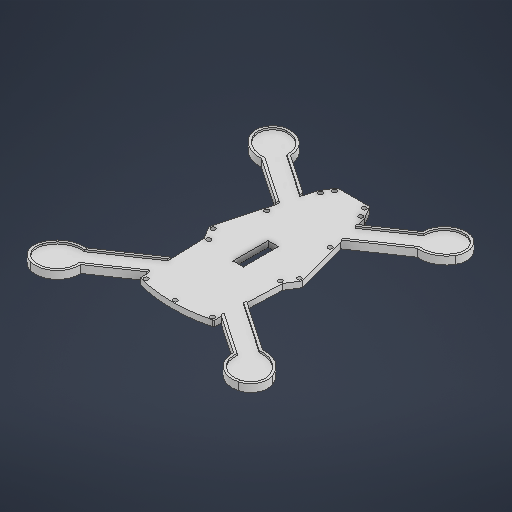
# Autodesk Inventor part: baseFinal
Saved by Autodesk Inventor 2026 (Build 300175000, 175)
## iProperties
Created: 2026-10-27
Part Number: baseFinal
Material: Genérico
Document SubType Name: Modeling
Designer: Juan David
Density: 1 g/cm^3
Appearance: Valor por defecto
Author: Juan David
Autodesk Inventor part; units mm, degrees
ref_plane "YZ Plane" through (0, 0, 0) normal (1, 0, 0) x (0, 1, 0)
ref_plane "XZ Plane" through (0, 0, 0) normal (0, 1, 0) x (-1, 0, 0)
ref_plane "XY Plane" through (0, 0, 0) normal (0, 0, 1) x (1, 0, 0)
sketch "Boceto1" plane through (0, 0, 0) normal (0, 1, 0) x (-1, 0, 0)
  line L0 (0, -150) -> (0, 150) construction
  line L1 (30.9916, 147.5712) -> (32.9123, 92.5712)
  arc A0 (30.9916, 147.5712) -> (30.2412, 148.5049) centre (29.9922, 147.5363) ccw
  line L2 (30.9916, 147.5712) -> (30.9916, 113.5172) construction
  line L3 (32.9123, 92.5712) -> (32.9123, 56.093) construction
  line L4 (32.9123, 92.5712) -> (39.3857, 82.2916)
  line L5 (39.3857, 82.2916) -> (19.8163, 10.2644)
  line L6 (19.8163, 10.2644) -> (19.8163, 47.3861) construction
  line L7 (19.8163, 10.2644) -> (13.6, 0)
  line L8 (13.6, 0) -> (13.6, 36.8341) construction
  line L9 (0, 0) -> (13.6, 0)
  line L10 (31.8621, 149.7984) -> (31.8621, 95.4867) construction
  line L11 (31.165, 142.6049) -> (64.2011, 165.1574)
  line L12 (31.8878, 121.9093) -> (74.0679, 150.7042)
  line L13 (54.2398, 179.7492) -> (74.1624, 150.5657) construction
  arc A1 (87.3177, 184.2934) -> (64.2011, 165.1574) centre (82.7685, 166.2583) ccw
  arc A2 (97.2377, 165.1659) -> (87.3177, 184.2934) centre (83.7957, 170.3307) ccw
  arc A3 (74.0679, 150.7042) -> (97.2377, 165.1659) centre (76.0608, 173.3027) ccw
  line L14 (31.165, 142.6049) -> (43.7776, 124.1294) construction
  line L15 (-112.3542, 46.9093) -> (112.3542, 46.9093) construction
  line L16 (130.9594, 121.9093) -> (-67.1839, 121.9093) construction
  line L17 (-124.1928, 84.4093) -> (124.1928, 84.4093) construction
  line L18 (45.548, -17.1271) -> (65.3642, 11.9007) construction
  arc A4 (55.4975, -2.5526) -> (75.66, -20.7594) centre (74.0946, -2.2254) ccw
  arc A5 (75.66, -20.7594) -> (86.7708, 1.04) centre (74.4481, -6.4105) ccw
  arc A6 (86.7708, 1.04) -> (65.3642, 11.9007) centre (67.3572, -10.6978) ccw
  line L19 (55.4975, -2.5526) -> (22.4614, 20)
  line L20 (22.4614, 20) -> (22.4614, -42.0773) construction
  line L21 (65.3642, 11.9007) -> (27.3176, 37.8738)
  line L22 (35.803, 41.6229) -> (22.4614, 20) construction
  line L23 (-30.9916, 147.5712) -> (-32.9123, 92.5712)
  arc A7 (-30.2412, 148.5049) -> (-30.9916, 147.5712) centre (-29.9922, 147.5363) ccw
  line L24 (-30.9916, 147.5712) -> (-30.9916, 113.5172) construction
  line L25 (-32.9123, 92.5712) -> (-32.9123, 56.093) construction
  line L26 (-32.9123, 92.5712) -> (-39.3857, 82.2916)
  line L27 (-39.3857, 82.2916) -> (-19.8163, 10.2644)
  line L28 (-19.8163, 10.2644) -> (-19.8163, 47.3861) construction
  line L29 (-19.8163, 10.2644) -> (-13.6, 0)
  line L30 (-13.6, 0) -> (-13.6, 36.8341) construction
  line L31 (0, 0) -> (-13.6, 0)
  line L32 (-31.8621, 149.7984) -> (-31.8621, 95.4867) construction
  line L33 (-31.165, 142.6049) -> (-64.2011, 165.1574)
  line L34 (-31.8878, 121.9093) -> (-74.0679, 150.7042)
  line L35 (-54.2398, 179.7492) -> (-74.1624, 150.5657) construction
  arc A8 (-64.2011, 165.1574) -> (-87.3177, 184.2934) centre (-82.7685, 166.2583) ccw
  arc A9 (-87.3177, 184.2934) -> (-97.2377, 165.1659) centre (-83.7957, 170.3307) ccw
  arc A10 (-97.2377, 165.1659) -> (-74.0679, 150.7042) centre (-76.0608, 173.3027) ccw
  line L36 (-31.165, 142.6049) -> (-43.7776, 124.1294) construction
  line L37 (-45.548, -17.1271) -> (-65.3642, 11.9007) construction
  arc A11 (-65.3642, 11.9007) -> (-86.7708, 1.04) centre (-67.3572, -10.6978) ccw
  arc A12 (-75.66, -20.7594) -> (-55.4975, -2.5526) centre (-74.0946, -2.2254) ccw
  arc A13 (-86.7708, 1.04) -> (-75.66, -20.7594) centre (-74.4481, -6.4105) ccw
  line L38 (-55.4975, -2.5526) -> (-22.4614, 20)
  line L39 (-22.4614, 20) -> (-22.4614, -42.0773) construction
  line L40 (-65.3642, 11.9007) -> (-27.3176, 37.8738)
  line L41 (-35.803, 41.6229) -> (-22.4614, 20) construction
  arc A14 (30.2412, 148.5049) -> (-30.2412, 148.5049) centre (0, 30.8422) ccw
  line L42 (4.35, 97.0416) -> (-4.35, 97.0416)
  line L43 (-4.35, 97.0416) -> (-4.35, 67.5416)
  line L44 (-4.35, 67.5416) -> (4.35, 67.5416)
  line L45 (4.35, 67.5416) -> (4.35, 97.0416)
  line L46 (4.35, 97.0416) -> (-4.35, 67.5416) construction
  line L47 (-4.35, 97.0416) -> (4.35, 67.5416) construction
  point P0 (31.8621, 122.6425)
  point P1 (96.5789, 176.9603)
  point P2 (0, 46.9093)
  point P3 (0, 84.4093)
  point P4 (-31.8621, 122.6425)
  point P5 (-96.5789, 176.9603)
  point P6 (0, 152.329)
  point P7 (0, 82.2916)
  point P8 (87.2778, -12.9496)
  dimension "d0" = 300
  dimension "d2" = 1
  dimension "d4" = 2
  dimension "d9" = 15.2
  dimension "d10" = 31.2
  dimension "d11" = 13.6
  dimension "d14" = 32.2
  dimension "d19" = 55
  dimension "d20" = 12
  dimension "d22" = 55.68
  dimension "d23" = 90
  dimension "d24" = 40
  dimension "d25" = 17.5
  dimension "d26" = 18.6
  dimension "d27" = 14.4
  dimension "d28" = 22.6863
  dimension "d29" = 5.9
  dimension "d37" = 75
  dimension "d38" = 37.5
  dimension "d41" = 55.68
  dimension "d43" = 40
  dimension "d44" = 90
  dimension "d45" = 17.5
  dimension "d47" = 20
  dimension "d48" = 121.4867
  dimension "d49" = 152.3289
  dimension "d50" = 8.7
  dimension "d51" = 29.5
  dimension "d54" = 10.2796
  dimension "d55" = 67.5416
  dimension "d69" = 67.4958
  dimension "d70" = 48.4214
  dimension "d71" = 78.6018
  dimension "d72" = 51.9867
  constraints: 98 end point, 40 symmetric about line, 35 point on circle, 17 point on line, 15 centre point, 8 midpoint, 7 vertical, 6 tangent, 4 horizontal, 4 parallel, 3 equal radius, 3 perpendicular, 1 horizontal alignment, 7 other
  measures "d0" distance of L0.start L0.end
  measures "d2" radius of A0
  measures "d4" angle of L1 L2
  measures "d9" angle of L6 L5
  measures "d10" angle of L8 L7
  measures "d11" distance of L9.start L7.end
  measures "d14" angle of L4 L3
  measures "d19" vertical distance of L1.start L1.end
  measures "d20" distance of L5.end L7.end
  measures "d22" angle of L10 L11
  measures "d23" angle of L13 L11
  measures "d24" distance of L11.start L11.end
  measures "d25" distance between parallel lines of L11 L12
  measures "d26" radius of A1
  measures "d27" radius of A2
  measures "d28" radius of A3
  measures "d29" vertical distance of A0.end L11.start
  measures "d37" distance between parallel lines of L16 L15
  measures "d38" distance between parallel lines of L16 L17
  measures "d41" angle of L19 L20
  measures "d43" distance of L19.start L19.end
  measures "d44" angle of L19 L18
  measures "d45" distance between parallel lines of L19 L21
  measures "d47" vertical distance of L19.end L7.end
  measures "d48" radius of A14
  measures "d49" distance of L9.start point (0, 152.329)
  measures "d50" distance of L43.end L44.end
  measures "d51" distance between parallel lines of L42 L44
  measures "d54" vertical distance of L1.end L4.end
  measures "d55" distance between parallel lines of L31 L44
  measures "d69" distance of L12.start A1.centre
  measures "d70" vertical distance of A2.centre L12.start
  measures "d71" distance of L21.end point (87.278, -12.95)
  measures "d72" horizontal distance of L19.end A5.centre
extrude "Extrusión1" add sketch "Boceto1" along normal blind 5
sketch "Boceto2" plane through (0, 5, 0) normal (0, 1, 0) x (1, 0, 0)
  line L0 (-11.4093, -7) -> (11.6701, -7) construction
  line L1 (13.6, 0) -> (-13.6, 0) construction
  line L2 (-11.4093, -7) -> (-14.1476, -11.5214) construction
  line L3 (-14.1476, -11.5214) -> (-33.1211, -81.3554) construction
  line L4 (-33.1211, -81.3554) -> (-27.1704, -90.8048) construction
  line L5 (-27.1704, -90.8048) -> (-25.3063, -144.186) construction
  line L6 (-13.6, 0) -> (-19.8163, -10.2644) construction
  line L7 (-19.8163, -10.2644) -> (-22.4614, -20) construction
  line L8 (-39.3857, -82.2916) -> (-32.9123, -92.5712) construction
  line L9 (-32.9123, -92.5712) -> (-31.8878, -121.9093) construction
  line L10 (-11.4093, -7) -> (-13.6, 0) construction
  line L11 (-19.8163, -10.2644) -> (-14.1476, -11.5214) construction
  line L12 (-27.3176, -37.8738) -> (-39.3857, -82.2916) construction
  line L13 (-33.1211, -81.3554) -> (-39.3857, -82.2916) construction
  line L14 (-32.9123, -92.5712) -> (-27.1704, -90.8048) construction
  line L15 (-16.982, -10.8929) -> (-36.2534, -81.8235) construction
  arc A0 (-24.5167, -145.1289) -> (24.5167, -145.1289) centre (0, -30.8422) ccw construction
  arc A1 (-30.2412, -148.5049) -> (30.2412, -148.5049) centre (0, -30.8422) ccw construction
  arc A2 (-25.3063, -144.186) -> (-24.5167, -145.1289) centre (-24.3069, -144.1511) ccw construction
  line L16 (-25.0736, -144.7932) -> (-30.7716, -148.1629) construction
  arc A3 (-30.9916, -147.5712) -> (-30.2412, -148.5049) centre (-29.9922, -147.5363) ccw construction
  line L17 (0, -147.729) -> (0, -152.329) construction
  circle A4 centre (-12.5047, -3.5) radius 1.86
  circle A5 centre (-16.982, -10.8929) radius 1.86
  circle A6 centre (-26.6177, -46.3582) radius 1.86
  circle A7 centre (-36.2534, -81.8235) radius 1.86
  circle A8 centre (-30.0413, -91.688) radius 1.86
  circle A9 centre (-27.9226, -146.478) radius 1.86
  circle A10 centre (0, -150.029) radius 1.86
  circle A11 centre (12.5047, -3.5) radius 1.86
  circle A12 centre (16.982, -10.8929) radius 1.86
  circle A13 centre (26.6177, -46.3582) radius 1.86
  circle A14 centre (36.2534, -81.8235) radius 1.86
  circle A15 centre (30.0413, -91.688) radius 1.86
  circle A16 centre (27.9226, -146.478) radius 1.86
  point P0 (0, 0)
  point P1 (-25.2792, -144.9626)
  dimension "d59" = 7
  dimension "d60" = 5.5
  dimension "d61" = 5.8
  dimension "d62" = 5.8
  dimension "d63" = 5.8
  dimension "d64" = 4.6
  dimension "d65" = 1
  dimension "d66" = 3.72
  constraints: 24 end point, 15 centre point, 10 point on circle, 7 midpoint, 6 equal radius, 6 symmetric about line, 4 parallel, 2 coincident, 2 tangent, 1 concentric, 1 horizontal, 1 point on line, 1 vertical, 1 vertical alignment, 6 other
  measures "d59" distance between parallel lines of L0 L1
  measures "d60" distance between parallel lines of L6 L2
  measures "d61" distance between parallel lines of L3 L7
  measures "d62" distance between parallel lines of L8 L4
  measures "d63" distance between parallel lines of L9 L5
  measures "d64" distance of L17.end L17.start
  measures "d65" radius of A2
  measures "d66" diameter of A4
extrude "Extrusión2" cut sketch "Boceto2" against normal blind 10
sketch "Boceto4" plane through (0, 5, 0) normal (0, 1, 0) x (1, 0, 0)
  line L0 (-22.4614, -20) -> (-55.4975, 2.5526) projected
  arc A0 (-55.4975, 2.5526) -> (-75.66, 20.7594) centre (-74.0946, 2.2254) ccw projected
  line L1 (-22.6363, -19.8807) -> (-55.4975, 2.5526)
  line L2 (-57.5103, 1.505) -> (-23.1913, -21.9234)
  line L3 (-23.1913, -21.9234) -> (-22.6363, -19.8807)
  line L4 (-19.8163, -10.2644) -> (-22.4614, -20) projected
  line L5 (-65.3642, -11.9007) -> (-27.3176, -37.8738) projected
  line L6 (-65.3642, -11.9007) -> (-27.4925, -37.7545)
  line L7 (-27.4925, -37.7545) -> (-26.9375, -35.7117)
  line L8 (-26.9375, -35.7117) -> (-64.8429, -9.835)
  line L9 (-27.3176, -37.8738) -> (-39.3857, -82.2916) projected
  arc A1 (-75.66, 20.7594) -> (-86.7708, -1.04) centre (-74.4481, 6.4105) ccw projected
  arc A2 (-86.7708, -1.04) -> (-65.3642, -11.9007) centre (-67.3572, 10.6978) ccw projected
  arc A3 (-57.5103, 1.505) -> (-75.4917, 18.7665) centre (-74.0946, 2.2254) ccw
  arc A4 (-75.4917, 18.7665) -> (-85.0593, -0.0052) centre (-74.4481, 6.4105) ccw
  arc A5 (-85.0593, -0.0052) -> (-64.8429, -9.835) centre (-67.3572, 10.6978) ccw
  line L10 (-31.8878, -121.9093) -> (-74.0679, -150.7042) projected
  line L11 (-32.0832, -122.0427) -> (-74.0679, -150.7042)
  line L12 (-73.5465, -152.7698) -> (-32.0006, -124.4079)
  line L13 (-32.0006, -124.4079) -> (-32.0832, -122.0427)
  line L14 (-32.9123, -92.5712) -> (-31.8878, -121.9093) projected
  line L15 (-64.2011, -165.1574) -> (-31.165, -142.6049) projected
  line L16 (-64.2011, -165.1574) -> (-31.3605, -142.7383)
  line L17 (-31.3605, -142.7383) -> (-31.4431, -140.3731)
  line L18 (-31.4431, -140.3731) -> (-66.3005, -164.169)
  line L19 (-64.2011, -165.1574) -> (-31.165, -142.6049) projected
  line L20 (-31.165, -142.6049) -> (-30.9916, -147.5712) projected
  arc A6 (-73.5465, -152.7698) -> (-95.3707, -165.8833) centre (-76.0608, -173.3027) ccw
  arc A7 (-74.0679, -150.7042) -> (-97.2377, -165.1659) centre (-76.0608, -173.3027) ccw projected
  arc A8 (-97.2377, -165.1659) -> (-87.3177, -184.2934) centre (-83.7957, -170.3307) ccw projected
  arc A9 (-87.3177, -184.2934) -> (-64.2011, -165.1574) centre (-82.7685, -166.2583) ccw projected
  arc A10 (-95.3707, -165.8833) -> (-86.8285, -182.3541) centre (-83.7957, -170.3307) ccw
  arc A11 (-86.8285, -182.3541) -> (-66.3005, -164.169) centre (-82.7685, -166.2583) ccw
  line L21 (0, 0) -> (0, -152.329) construction
  arc A12 (-30.2412, -148.5049) -> (30.2412, -148.5049) centre (0, -30.8422) ccw construction
  arc A13 (-86.7708, -1.04) -> (-65.3642, -11.9007) centre (-67.3572, 10.6978) ccw construction
  arc A14 (-75.66, 20.7594) -> (-86.7708, -1.04) centre (-74.4481, 6.4105) ccw construction
  arc A15 (-55.4975, 2.5526) -> (-75.66, 20.7594) centre (-74.0946, 2.2254) ccw construction
  arc A16 (-74.0679, -150.7042) -> (-97.2377, -165.1659) centre (-76.0608, -173.3027) ccw construction
  arc A17 (-97.2377, -165.1659) -> (-87.3177, -184.2934) centre (-83.7957, -170.3307) ccw construction
  arc A18 (-87.3177, -184.2934) -> (-64.2011, -165.1574) centre (-82.7685, -166.2583) ccw construction
  line L22 (22.4614, -20) -> (55.4975, 2.5526)
  arc A19 (75.66, 20.7594) -> (55.4975, 2.5526) centre (74.0946, 2.2254) ccw
  line L23 (57.5103, 1.505) -> (23.1913, -21.9234)
  line L24 (23.1913, -21.9234) -> (22.6363, -19.8807)
  line L25 (65.3642, -11.9007) -> (27.4925, -37.7545)
  line L26 (27.4925, -37.7545) -> (26.9375, -35.7117)
  line L27 (26.9375, -35.7117) -> (64.8429, -9.835)
  arc A20 (86.7708, -1.04) -> (75.66, 20.7594) centre (74.4481, 6.4105) ccw
  arc A21 (65.3642, -11.9007) -> (86.7708, -1.04) centre (67.3572, 10.6978) ccw
  arc A22 (75.4917, 18.7665) -> (57.5103, 1.505) centre (74.0946, 2.2254) ccw
  arc A23 (85.0593, -0.0052) -> (75.4917, 18.7665) centre (74.4481, 6.4105) ccw
  arc A24 (64.8429, -9.835) -> (85.0593, -0.0052) centre (67.3572, 10.6978) ccw
  line L28 (32.0832, -122.0427) -> (74.0679, -150.7042)
  line L29 (73.5465, -152.7698) -> (32.0006, -124.4079)
  line L30 (32.0006, -124.4079) -> (32.0832, -122.0427)
  line L31 (64.2011, -165.1574) -> (31.3605, -142.7383)
  line L32 (31.3605, -142.7383) -> (31.4431, -140.3731)
  line L33 (31.4431, -140.3731) -> (66.3005, -164.169)
  arc A25 (95.3707, -165.8833) -> (73.5465, -152.7698) centre (76.0608, -173.3027) ccw
  arc A26 (97.2377, -165.1659) -> (74.0679, -150.7042) centre (76.0608, -173.3027) ccw
  arc A27 (87.3177, -184.2934) -> (97.2377, -165.1659) centre (83.7957, -170.3307) ccw
  arc A28 (64.2011, -165.1574) -> (87.3177, -184.2934) centre (82.7685, -166.2583) ccw
  arc A29 (86.8285, -182.3541) -> (95.3707, -165.8833) centre (83.7957, -170.3307) ccw
  arc A30 (66.3005, -164.169) -> (86.8285, -182.3541) centre (82.7685, -166.2583) ccw
  dimension "d76" = 0.2
  dimension "d78" = 2
  dimension "d79" = 2
  dimension "d80" = 0.2
  dimension "d82" = 2
  dimension "d83" = 0.2
  dimension "d84" = 2
  dimension "d85" = 0.2
  dimension "d86" = 2
  dimension "d87" = 2
  constraints: 50 end point, 49 point on circle, 37 symmetric about line, 24 centre point, 12 coincident, 8 parallel, 8 tangent, 6 point on line, 4 concentric, 1 collinear, 1 vertical, 12 other
  measures "d76" distance between parallel lines of L3 L4
  measures "d78" distance between parallel lines of L0 L2
  measures "d79" distance between parallel lines of L8 L5
  measures "d80" distance between parallel lines of L9 L7
  measures "d82" radial gap between concentric circles of A3 A0
  measures "d83" distance between parallel lines of L13 L14
  measures "d84" distance between parallel lines of L11 L12
  measures "d85" distance between parallel lines of L17 L20
  measures "d86" distance between parallel lines of L16 L18
  measures "d87" radial gap between concentric circles of A7 A6
extrude "Extrusión3" add sketch "Boceto4" along normal blind 1.5
